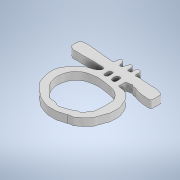
# Autodesk Inventor part: litera_O_pe_bara
Saved by Autodesk Inventor 2022.6 (Build 266554000, 554)
## iProperties
Created: 2024-11-30
Part Number: litera_O_pe_bara
Material: Generic
Document SubType Name: Modeling
Designer: Dragos Macovei
Density: 1 g/cm^3
Appearance: Default
Author: Dragos Macovei
Autodesk Inventor part; units mm, degrees
ref_plane "YZ Plane" through (0, 0, 0) normal (1, 0, 0) x (0, 1, 0)
ref_plane "XZ Plane" through (0, 0, 0) normal (0, 1, 0) x (-1, 0, 0)
ref_plane "XY Plane" through (0, 0, 0) normal (0, 0, 1) x (1, 0, 0)
sketch "Sketch1" plane through (0, 0, 0) normal (0, 1, 0) x (-1, 0, 0)
  line L0 (0, 0) -> (40, 0)
  line L1 (40, 0) -> (40, 40)
  line L2 (40, 40) -> (0, 40)
  line L3 (0, 40) -> (0, 0)
  line L4 (-196.5906, 402.5123) -> (209.8094, 402.5123) construction
  line L5 (209.8094, 402.5123) -> (209.8094, -139.3544) construction
  line L6 (209.8094, -139.3544) -> (-196.5906, -139.3544) construction
  line L7 (-196.5906, -139.3544) -> (-196.5906, 402.5123) construction
  spline S0 degree 4 poles (19.4343, 14.466) (19.5542, 14.8313) (19.7473, 14.7864) (20.4813, 14.9074) (20.5698, 14.0889) (20.665, 13.4311) (20.6053, 12.8647) (20.5818, 12.1197) (19.8863, 12.0344) (19.0532, 11.8983) (19.212, 12.6849) (19.065, 12.8741) (19.0832, 13.9103) (19.0981, 14.2476) (19.2391, 14.6045) (19.4343, 14.466) knots 0 0 0 0 0 0.149163 0.215943 0.288042 0.363363 0.440988 0.516921 0.59027 0.659527 0.729862 0.798974 0.864322 1 1 1 1 1
  spline S1 degree 5 poles (17.3818, 14.466) (17.3618, 14.5574) (17.3274, 14.7019) (17.2549, 14.8896) (16.9676, 14.9513) (16.6274, 15.0697) (16.2676, 15.1354) (15.9192, 14.8277) (15.6765, 14.7068) (15.7817, 14.1034) (15.5789, 13.7094) (15.8934, 13.123) (15.7042, 12.7625) (15.8981, 12.1533) (16.9863, 12.3727) (17.2541, 12.3374) (17.6469, 12.9234) (17.5696, 13.7414) (17.4554, 14.105) (17.4105, 14.3353) (17.3818, 14.466) knots 0 0 0 0 0 0 0.063608 0.106551 0.160721 0.213632 0.26879 0.325903 0.385391 0.445517 0.50792 0.574675 0.640312 0.706089 0.777861 0.851729 0.90901 1 1 1 1 1 1
  spline S2 degree 5 poles (19.2463, 34.264) (18.9965, 34.3473) (18.5705, 34.3865) (17.8892, 34.1279) (16.9728, 33.7861) (16.1032, 33.6755) (14.8051, 33.0707) (14.0851, 32.7919) (13.2962, 31.8672) (11.9164, 32.4456) (11.7808, 31.6309) (11.0939, 30.8424) (10.8271, 30.2402) (10.4285, 29.656) (9.7622, 29.0403) (9.8116, 28.3413) (9.6593, 27.2702) (9.6674, 26.0441) (9.4376, 25.1679) (9.6929, 23.1899) (9.6137, 22.5741) (9.7652, 20.944) (10.8824, 19.7567) (11.8319, 18.6429) (14.1133, 17.3282) (17.2024, 17.316) (20.0903, 16.3536) (23.1965, 17.1234) (25.2366, 17.4146) (26.6796, 18.7132) (28.1254, 20.0543) (28.6797, 21.6784) (28.9304, 22.6397) (29.2508, 25.2247) (28.9446, 25.6745) (28.5277, 27.524) (28.1585, 28.1323) (27.0754, 29.4554) (26.4058, 29.9713) (25.8317, 30.5308) (24.7205, 31.6122) (24.1117, 32.535) (23.2884, 33.3585) (22.0113, 33.5366) (20.6809, 33.2505) (19.9852, 33.8887) (19.5289, 34.1698) (19.2463, 34.264) knots 0 0 0 0 0 0 0.025432 0.042723 0.063995 0.08525 0.106088 0.126067 0.145399 0.164135 0.18207 0.199523 0.216998 0.234573 0.253201 0.27291 0.294314 0.316398 0.338905 0.361841 0.385259 0.409571 0.437323 0.468198 0.501312 0.53521 0.568457 0.599792 0.628401 0.654754 0.681136 0.706253 0.730628 0.754358 0.778059 0.799817 0.821078 0.84235 0.863917 0.884872 0.906583 0.929667 0.952705 0.971218 1 1 1 1 1 1
  spline S3 degree 5 poles (13.9003, 35.4258) (13.669, 35.3377) (13.3066, 35.1888) (12.8265, 35.0249) (11.8102, 35.3612) (11.3502, 34.4066) (10.0819, 33.5742) (9.4913, 33.3109) (8.6365, 32.2492) (8.1274, 31.6552) (7.4597, 30.7896) (7.5789, 29.7336) (6.9122, 29.2782) (6.7566, 27.3866) (6.0106, 27.0504) (6.1349, 25.628) (5.9896, 24.4499) (5.9297, 23.3396) (6.2506, 21.8208) (6.9624, 20.8796) (7.2641, 19.2854) (8.2778, 18.2239) (9.4328, 17.0657) (10.3947, 16.1431) (12.058, 15.8587) (12.9052, 15.8103) (13.9256, 15.6839) (13.4309, 15.0089) (13.6607, 14.399) (13.4982, 13.9232) (13.5491, 13.385) (13.6076, 12.9862) (13.0983, 12.7206) (12.6358, 12.7329) (11.5812, 12.646) (11.3554, 12.0098) (10.6371, 13.276) (10.0797, 12.6626) (8.6994, 13.3562) (8.4384, 13.3807) (7.4086, 13.8288) (6.5535, 13.721) (5.6382, 14.1765) (4.4251, 13.8647) (3.8342, 14.3326) (2.6281, 14.0141) (2.1651, 13.8798) (2.5639, 12.7908) (2.145, 12.3081) (2.3806, 11.4087) (2.4164, 10.6263) (1.9006, 9.9273) (4.55, 9.3092) (5.306, 8.8706) (7.5005, 9.325) (9.0165, 8.6901) (11.0575, 9.1647) (12.3221, 8.2197) (14.2033, 9.3311) (14.0241, 7.8205) (14.2296, 7.3013) (13.5522, 6.2108) (15.688, 5.8683) (16.0206, 6.2163) (15.6856, 7.1335) (16.1481, 7.6512) (15.5357, 8.7109) (16.716, 8.291) (17.3632, 8.9408) (17.0893, 7.4894) (17.2889, 7.2547) (17.4086, 6.4345) (17.3835, 5.9615) (19.2479, 5.4525) (18.4774, 6.706) (19.3863, 6.7545) (19.079, 7.5749) (19.5448, 8.186) (19.415, 8.4891) (21.0712, 8.5625) (20.1943, 7.2707) (21.3867, 6.8102) (20.7441, 6.0248) (23.1224, 5.5843) (22.1378, 6.7912) (23.2119, 7.5583) (22.3182, 8.8265) (24.6416, 8.0933) (26.4046, 8.2912) (28.3238, 7.869) (31.2195, 7.7096) (33.3387, 7.378) (35.8123, 7.3882) (36.7325, 7.9381) (36.9782, 9.5483) (36.7006, 10.1352) (36.8758, 11.8648) (35.4961, 11.2945) (35.6476, 12.6448) (33.5499, 11.689) (32.2585, 12.4022) (30.1132, 11.9421) (27.6892, 12.2739) (26.5452, 11.9034) (24.747, 12.4249) (23.6507, 12.1264) (21.9358, 12.3058) (22.8507, 14.0562) (23.2462, 14.1253) (24.6299, 15.0621) (26.0463, 15.1876) (27.3969, 15.6908) (28.3964, 16.801) (29.4965, 17.595) (30.3418, 19.2812) (31.0717, 19.8415) (32.2372, 22.1716) (32.0984, 24.0235) (31.9356, 25.8279) (31.3948, 27.2977) (30.6585, 30.0837) (29.9079, 30.4533) (28.4734, 32.5377) (27.015, 32.8884) (26.0161, 34.5221) (24.2404, 35.1604) (23.0386, 35.8119) (20.1789, 36.7121) (19.7052, 36.1982) (17.4419, 36.6954) (16.2469, 36.0389) (15.5142, 35.8752) (14.6508, 35.6973) (14.1626, 35.5256) (13.9003, 35.4258) knots 0 0 0 0 0 0 0.00858 0.014625 0.022097 0.029703 0.037308 0.044894 0.052098 0.059244 0.066648 0.074039 0.081555 0.089352 0.097375 0.105311 0.113504 0.121921 0.130518 0.139418 0.148431 0.157615 0.166496 0.174509 0.181657 0.188113 0.193804 0.199051 0.204191 0.209188 0.214149 0.219461 0.224715 0.230352 0.236363 0.242857 0.249075 0.255656 0.262424 0.269432 0.276399 0.283608 0.290925 0.29776 0.30437 0.310645 0.316831 0.322831 0.328967 0.335651 0.343075 0.351198 0.360134 0.370063 0.380114 0.389651 0.398447 0.406448 0.413675 0.420735 0.427328 0.433881 0.440435 0.446809 0.452651 0.458544 0.464506 0.47033 0.476183 0.481979 0.488206 0.494305 0.500304 0.50634 0.512324 0.517711 0.523236 0.52908 0.535088 0.541177 0.547938 0.554616 0.561405 0.568045 0.574763 0.582178 0.590587 0.600114 0.610914 0.622465 0.633251 0.643385 0.652438 0.660482 0.667664 0.674471 0.681255 0.688568 0.696696 0.705925 0.715844 0.726056 0.735974 0.745012 0.753243 0.760965 0.768518 0.776206 0.784278 0.792625 0.801454 0.810438 0.819196 0.828346 0.837869 0.847554 0.857473 0.867967 0.877993 0.887946 0.897846 0.907602 0.917052 0.926832 0.936792 0.946497 0.956315 0.965873 0.974915 0.983399 0.990268 1 1 1 1 1 1
  point P0 (19.6694, 14.7716)
  point P1 (20, 14.7951)
  point P2 (20.3745, 14.6541)
  point P3 (20.5626, 14.1604)
  point P4 (20.6331, 13.4553)
  point P5 (20.6096, 12.8206)
  point P6 (20.4451, 12.2565)
  point P7 (19.8104, 12.0214)
  point P8 (19.2228, 12.1155)
  point P9 (19.1523, 12.5856)
  point P10 (19.1052, 12.9382)
  point P11 (19.0817, 13.6903)
  point P12 (19.1288, 14.2075)
  point P13 (19.2463, 14.466)
  point P14 (17.0003, 14.9479)
  point P15 (16.6395, 15.051)
  point P16 (16.2786, 15.051)
  point P17 (15.9487, 14.8654)
  point P18 (15.7735, 14.6541)
  point P19 (15.7219, 14.2075)
  point P20 (15.691, 13.6903)
  point P21 (15.7838, 13.1643)
  point P22 (15.7941, 12.7416)
  point P23 (16.0106, 12.3807)
  point P24 (16.8354, 12.3292)
  point P25 (17.2478, 12.4632)
  point P26 (17.5158, 12.9382)
  point P27 (17.5055, 13.8963)
  point P28 (17.0634, 33.8642)
  point P29 (16.0639, 33.5843)
  point P30 (14.8644, 33.1046)
  point P31 (14.0248, 32.6248)
  point P32 (13.0652, 32.185)
  point P33 (12.1056, 32.105)
  point P34 (11.6658, 31.6252)
  point P35 (11.146, 30.8256)
  point P36 (10.7862, 30.2258)
  point P37 (10.3864, 29.6661)
  point P38 (9.9466, 29.0663)
  point P39 (9.7866, 28.4266)
  point P40 (9.7067, 27.4271)
  point P41 (9.6267, 26.2276)
  point P42 (9.5467, 25.0281)
  point P43 (9.6267, 23.3889)
  point P44 (9.6667, 22.4293)
  point P45 (9.9066, 21.2298)
  point P46 (10.6662, 20)
  point P47 (11.7058, 18.9508)
  point P48 (13.6649, 17.8313)
  point P49 (16.9435, 17.1516)
  point P50 (20.4451, 16.7518)
  point P51 (23.5006, 17.1516)
  point P52 (25.3797, 17.7913)
  point P53 (26.8191, 18.8709)
  point P54 (28.0186, 20.2702)
  point P55 (28.6183, 21.5897)
  point P56 (28.9381, 22.989)
  point P57 (29.0981, 24.9882)
  point P58 (28.8982, 26.0277)
  point P59 (28.4983, 27.3471)
  point P60 (27.9786, 28.3067)
  point P61 (27.059, 29.3862)
  point P62 (26.4193, 29.9859)
  point P63 (25.8195, 30.5457)
  point P64 (24.86, 31.5452)
  point P65 (24.0603, 32.5048)
  point P66 (23.2207, 33.1845)
  point P67 (21.9812, 33.4244)
  point P68 (20.4451, 33.6243)
  point P69 (12.0749, 35.0813)
  point P70 (11.2828, 34.5303)
  point P71 (10.1807, 33.6693)
  point P72 (9.423, 33.1182)
  point P73 (8.6653, 32.2916)
  point P74 (8.0798, 31.5684)
  point P75 (7.632, 30.7418)
  point P76 (7.4254, 29.9152)
  point P77 (7.081, 29.1231)
  point P78 (6.6094, 27.6766)
  point P79 (6.22, 26.85)
  point P80 (6.0822, 25.7479)
  point P81 (6.0133, 24.508)
  point P82 (6.0133, 23.337)
  point P83 (6.3233, 21.9938)
  point P84 (6.8399, 20.8229)
  point P85 (7.391, 19.4797)
  point P86 (8.2864, 18.2398)
  point P87 (9.4574, 17.0688)
  point P88 (10.7662, 16.2078)
  point P89 (12.2816, 15.8634)
  point P90 (13.2722, 15.7287)
  point P91 (13.6172, 15.4891)
  point P92 (13.5788, 15.0003)
  point P93 (13.5788, 14.387)
  point P94 (13.5405, 13.8599)
  point P95 (13.5501, 13.3711)
  point P96 (13.4926, 13.0452)
  point P97 (13.2051, 12.8206)
  point P98 (12.6396, 12.7194)
  point P99 (11.7292, 12.5181)
  point P100 (11.3075, 12.4127)
  point P101 (10.7409, 12.8206)
  point P102 (10.0154, 12.9382)
  point P103 (8.8783, 13.2415)
  point P104 (8.3097, 13.4553)
  point P105 (7.5255, 13.6903)
  point P106 (6.6094, 13.8297)
  point P107 (5.5845, 14.0062)
  point P108 (4.467, 14.0454)
  point P109 (3.5847, 14.1604)
  point P110 (2.6436, 13.9866)
  point P111 (2.3691, 13.6903)
  point P112 (2.3887, 12.9382)
  point P113 (2.2907, 12.2565)
  point P114 (2.3299, 11.477)
  point P115 (2.3299, 10.7516)
  point P116 (2.3495, 10.2222)
  point P117 (3.7023, 9.4968)
  point P118 (5.4276, 9.0851)
  point P119 (7.2706, 9.0851)
  point P120 (9.2312, 8.9282)
  point P121 (11.1918, 8.8106)
  point P122 (12.9367, 8.7126)
  point P123 (13.9003, 8.6537)
  point P124 (14.0935, 7.9479)
  point P125 (14.0543, 7.2029)
  point P126 (14.1327, 6.4383)
  point P127 (15.5443, 6.0658)
  point P128 (15.858, 6.3795)
  point P129 (15.858, 7.0657)
  point P130 (15.9168, 7.8107)
  point P131 (15.9364, 8.3793)
  point P132 (16.6422, 8.5165)
  point P133 (17.1324, 8.4969)
  point P134 (17.1912, 7.7323)
  point P135 (17.2696, 7.1441)
  point P136 (17.3818, 6.5559)
  point P137 (17.7402, 6.0069)
  point P138 (18.7205, 5.9089)
  point P139 (18.8577, 6.5167)
  point P140 (19.1288, 6.9284)
  point P141 (19.2463, 7.5558)
  point P142 (19.4343, 8.1244)
  point P143 (19.6694, 8.3793)
  point P144 (20.4451, 8.3204)
  point P145 (20.6331, 7.497)
  point P146 (20.9948, 6.752)
  point P147 (21.3477, 6.1638)
  point P148 (22.426, 5.9873)
  point P149 (22.5632, 6.6539)
  point P150 (22.7985, 7.6146)
  point P151 (22.8965, 8.2616)
  point P152 (23.6612, 8.3989)
  point P153 (25.9551, 8.1832)
  point P154 (28.1901, 7.9675)
  point P155 (31.2487, 7.6538)
  point P156 (34.0327, 7.4382)
  point P157 (35.9541, 7.6735)
  point P158 (36.6599, 8.3793)
  point P159 (36.856, 9.4772)
  point P160 (36.7775, 10.5163)
  point P161 (36.4638, 11.4378)
  point P162 (35.8561, 11.6731)
  point P163 (35.4247, 12.0214)
  point P164 (34.3464, 12.1155)
  point P165 (32.4446, 12.1155)
  point P166 (30.0723, 12.1155)
  point P167 (27.6608, 12.1155)
  point P168 (26.1903, 12.1155)
  point P169 (24.6611, 12.2565)
  point P170 (23.269, 12.2565)
  point P171 (22.5044, 12.7122)
  point P172 (22.7593, 13.6903)
  point P173 (23.3083, 14.2075)
  point P174 (24.4258, 14.7951)
  point P175 (25.9747, 15.2609)
  point P176 (27.3079, 15.8295)
  point P177 (28.4058, 16.7314)
  point P178 (29.4057, 17.7509)
  point P179 (30.2758, 18.9831)
  point P180 (31.0069, 20)
  point P181 (31.9068, 21.9638)
  point P182 (32.0755, 24.0447)
  point P183 (31.8505, 25.7319)
  point P184 (31.3444, 27.5878)
  point P185 (30.557, 29.7249)
  point P186 (29.7696, 30.7934)
  point P187 (28.4199, 32.1994)
  point P188 (27.1264, 33.1555)
  point P189 (25.8891, 34.264)
  point P190 (24.4268, 35.1239)
  point P191 (22.6834, 35.855)
  point P192 (20.4451, 36.4174)
  point P193 (19.2463, 36.4174)
  point P194 (17.3818, 36.4174)
  point P195 (16.1596, 36.08)
  point P196 (15.1472, 35.7988)
  dimension "d0" = 40
  dimension "d1" = 40
  constraints: 8 end point, 2 parallel, 1 horizontal, 1 perpendicular, 207 other
  measures "d0" distance of L2.end L1.end
  measures "d1" distance of L1.end L0.end
extrude "Extrusion1" add sketch "Sketch1" along normal blind 3 contours S3
body "Solid1"
